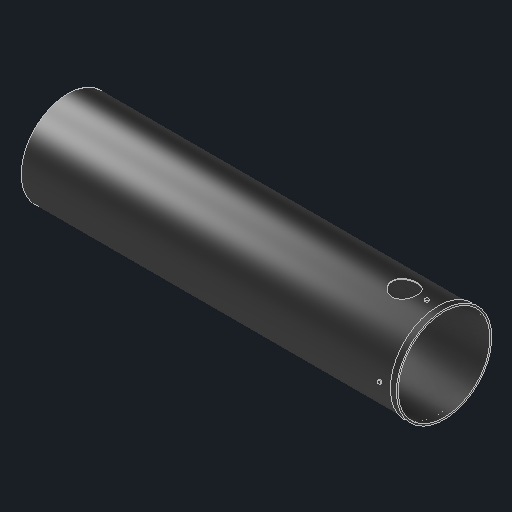
# Autodesk Inventor part: c8n_tube
Saved by Autodesk Inventor 2027.1 (Build 311270010, 270A)
## iProperties
Created: 2026-11-04
Part Number: c8n_tube
Material: Generic
Description: Celestron C8-N tube, 232 OD x 940 (estimated), 2 mm wall
Document SubType Name: Modeling
Designer: Claude (from photos)
Density: 1 g/cm^3
Appearance: Glossy - Black
Author: alexg
Autodesk Inventor part; units mm, degrees
ref_plane "Work Plane1" through (6, 0, 0) normal (1, 0, 0) x (0, 1, 0)
sketch "Tube 232 OD sketch" plane through (6, 0, 0) normal (1, 0, 0) x (0, 1, 0)
  circle A0 centre (0, 0) radius 116
  circle A1 centre (0, 0) radius 114
  constraints: 2 centre point
extrude "Tube 232 OD" add sketch "Tube 232 OD sketch" along normal blind 934
ref_plane "Work Plane2" through (925, 0, 0) normal (1, 0, 0) x (0, 1, 0)
sketch "Front ring sketch" plane through (925, 0, 0) normal (1, 0, 0) x (0, 1, 0)
  circle A0 centre (0, 0) radius 118.5
  circle A1 centre (0, 0) radius 115
  constraints: 2 centre point
extrude "Front ring" add sketch "Front ring sketch" along normal blind 15
sketch "Focuser hole sketch" plane through (0, 0, 0) normal (0, 1, 0) x (-1, 0, 0)
  circle A0 centre (-842, 0) radius 31
  constraints: 1 centre point
extrude "Focuser hole" cut sketch "Focuser hole sketch" along normal blind 150
ref_plane "Work Plane3" through (0, 115, 0) normal (0, 1, 0) x (-1, 0, 0)
sketch "Spider screw top sketch" plane through (0, 115, 0) normal (0, 1, 0) x (-1, 0, 0)
  circle A0 centre (-897, 0) radius 4.5
  constraints: 1 centre point
extrude "Spider screw top" add sketch "Spider screw top sketch" along normal blind 4
ref_plane "Work Plane4" through (0, -115, 0) normal (0, 1, 0) x (-1, 0, 0)
sketch "Spider screw bottom sketch" plane through (0, -115, 0) normal (0, 1, 0) x (-1, 0, 0)
  circle A0 centre (-897, 0) radius 4.5
  constraints: 1 centre point
extrude "Spider screw bottom" add sketch "Spider screw bottom sketch" against normal blind 4
ref_plane "Work Plane5" through (0, 0, 115) normal (0, 0, 1) x (1, 0, 0)
sketch "Spider screw +z sketch" plane through (0, 0, 115) normal (0, 0, 1) x (1, 0, 0)
  circle A0 centre (897, 0) radius 4.5
  constraints: 1 centre point
extrude "Spider screw +z" add sketch "Spider screw +z sketch" along normal blind 4
ref_plane "Work Plane6" through (0, 0, -115) normal (0, 0, 1) x (1, 0, 0)
sketch "Spider screw -z sketch" plane through (0, 0, -115) normal (0, 0, 1) x (1, 0, 0)
  circle A0 centre (897, 0) radius 4.5
  constraints: 1 centre point
extrude "Spider screw -z" add sketch "Spider screw -z sketch" against normal blind 4
body "Solid1"
